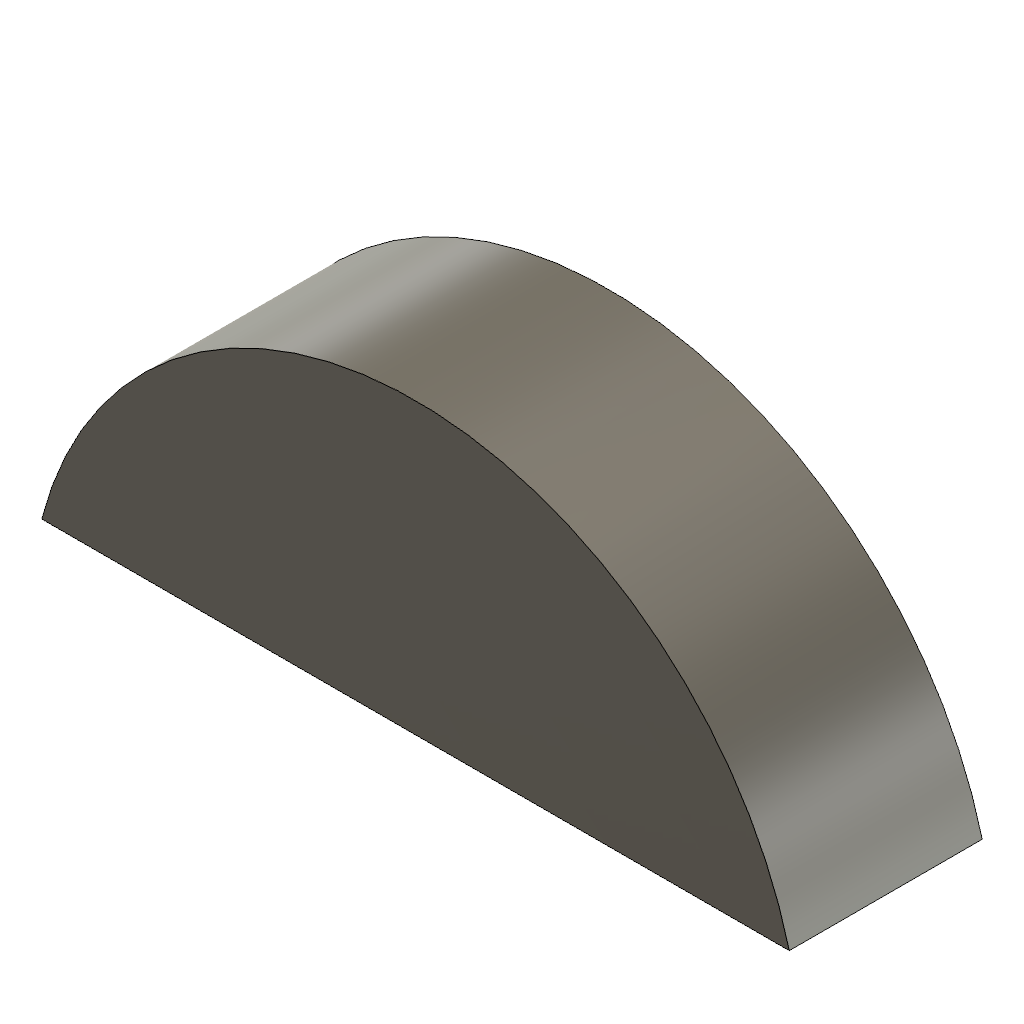
circle_line_segment (Autodesk Fusion 360 design; units mm, degrees)
part number: 2026-10-21-12-11-53-062
Autodesk Fusion 360 part; units mm, degrees
sketch "TrimmedProfileSources" plane through (0, 0, 0) normal (0, 0, 1) x (1, 0, 0)
  circle A0 centre (0, 0) radius 20
  line L0 (-30, 5) -> (30, 5)
extrude "SelectedTrimmedProfile" add sketch "TrimmedProfileSources" along normal blind 10 contours A0 L0 picked at (-0.0729, 13.007)
